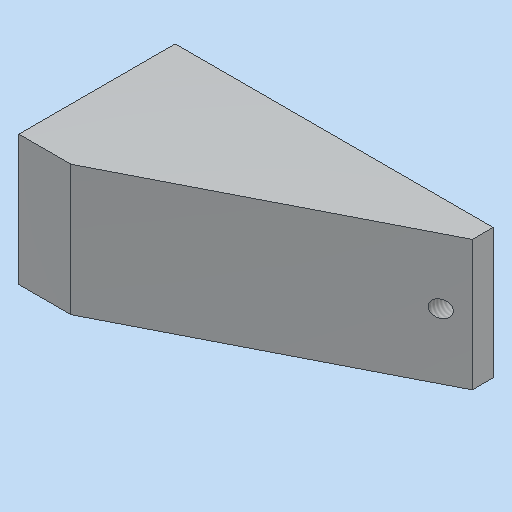
# Autodesk Inventor part: MM0948AN100_G01_110
Saved by Autodesk Inventor 2023.3 (Build 273359000, 359)
## iProperties
Part Number: MM0948AN100_G01_110
Material: 3.3547 AlMg4,5Mn0,7 - AW 5083
Description: =<RBPARTNOTITLE2>
Document SubType Name: Modeling
Designer: ric7an
Mass: 77.7559 g
Surface Area: 68.3139 cm^2
Volume: 28.7985 cm^3
Density: 2.7 g/cm^3
Appearance: Aluminium AnP
Created: 2023-03-23
RBDOCUMENTTYPE: DRF
RBDOCUMENTVERSION: 00
RBDRAWINGMAINSCALE: 1:1
RBDRAWINGMISSINGSPEC: --
RBDRAWINGVOLUME: --
RBGBEDGESIN1: +0,5
RBGBEDGESIN2: +0,2
RBGBEDGESOUT1: -0,3
RBGBEDGESOUT2: -0,1
RBMATERIAL: =<Material>
RBMATMEETS: --
RBMATNO: =<Part Number>
RBPARTMADEOF: 25 x 30 x 61 (FM)
RBPARTNO: SIEHE MNR
RBPARTNOTITLE1: manufactured part
RBPARTNOTITLE2: Anfertigungsteil
RBPARTSAFETYINDICATOR: --
RBSURFACE: anodised colourless
RBSURFACE2: eloxiert farblos
RBZEDGESNORM: ISO13715:2002-06
RBZGENDIMCLASS: m
RBZGENDIMNORM: ISO 2768-1:1989-11
RBZGENGEOCLASS: H
RBZGENGEONORM: ISO 2768-2:1989-11
RBZSURFACENORM: ISO13D2:2002-02
RBZTOLERANCENORM: ISO 14405-1:2010-12
AnP_Material: =<Material>
AnP_TemplVers: 20190222
AnP_Kategorie: 1
MaxAbmaße: 25 x 30 x 61 (FM)
AnP_Kommentar_aktuell: =<Comments>
AnP_Material_aktuell: =<Material>
Author: FH/Wi
Keywords: =<RBPARTMADEOF>
Comments: =<RBSURFACE2>
Revision Number: 01
Autodesk Inventor part; units mm, degrees
ref_plane "YZ Plane" through (0, 0, 0) normal (1, 0, 0) x (0, 1, 0)
ref_plane "XZ Plane" through (0, 0, 0) normal (0, 1, 0) x (-1, 0, 0)
ref_plane "XY Plane" through (0, 0, 0) normal (0, 0, 1) x (1, 0, 0)
sketch "Skizze1" plane through (0, 0, 0) normal (0, 0, 1) x (1, 0, 0)
  line L0 (61, 26) -> (61, 30)
  line L1 (61, 30) -> (0, 30)
  line L2 (0, 30) -> (0, 0)
  line L3 (0, 0) -> (10, 0)
  line L4 (10, 0) -> (61, 26)
  dimension "d0" = 30
  dimension "d1" = 61
  dimension "d2" = 4
  dimension "d14" = 10
  constraints: 10 end point, 2 perpendicular, 1 horizontal, 1 vertical
  measures "d0" distance of L1.end L2.end
  measures "d1" distance of L0.end L1.end
  measures "d2" distance of L0.start L0.end
  measures "d14" distance of L2.end L3.end
extrude "Extrusion1" add sketch "Skizze1" along normal mid plane 25
sketch "Skizze2" plane through (0, 0, 12.5) normal (-1, 0, 0) x (0, 0, 1)
  line L0 (-30, 0) -> (5, 0) projected
  line L1 (-12.5, 36) -> (-12.5, -6) projected
  point P0 (-12.5, 0)
  point P1 (-12.5, 22)
  point P2 (-12.5, 5)
  dimension "d5" = 17
  dimension "d6" = 5
  constraints: 2 point on line
  measures "d5" distance of point (-12.5, 5) point (-12.5, 22)
  measures "d6" distance from line of L0 point (-12.5, 5)
hole "Bohrung1" at (0, 22, 0) at (0, 5, 0) direction (1, 0, 0) diameter 3.242 depth 11.8 tip angle 118 thread size "M4x0.7" designation "M4" class "6H" standard "ISO Metric profile"
sketch "Skizze3" plane through (0, 30, 12.5) normal (0, 1, 0) x (1, 0, 0)
  line L0 (0, 30) -> (0, -5) projected
  line L1 (73.2, 12.5) -> (-12.2, 12.5) projected
  point P0 (0, 12.5)
  point P1 (16, 12.5)
  point P2 (57, 12.5)
  dimension "d15" = 41
  dimension "d16" = 16
  constraints: 2 point on line
  measures "d15" distance of point (57, 12.5) point (16, 12.5)
  measures "d16" distance from line of point (16, 12.5) L0
hole "Bohrung2" at (16, 30, 0) at (57, 30, 0) direction (0, -1, 0) diameter 3.242 depth 15 tip angle 118 thread size "M4x0.7" designation "M4" class "6H" standard "ISO Metric profile"
